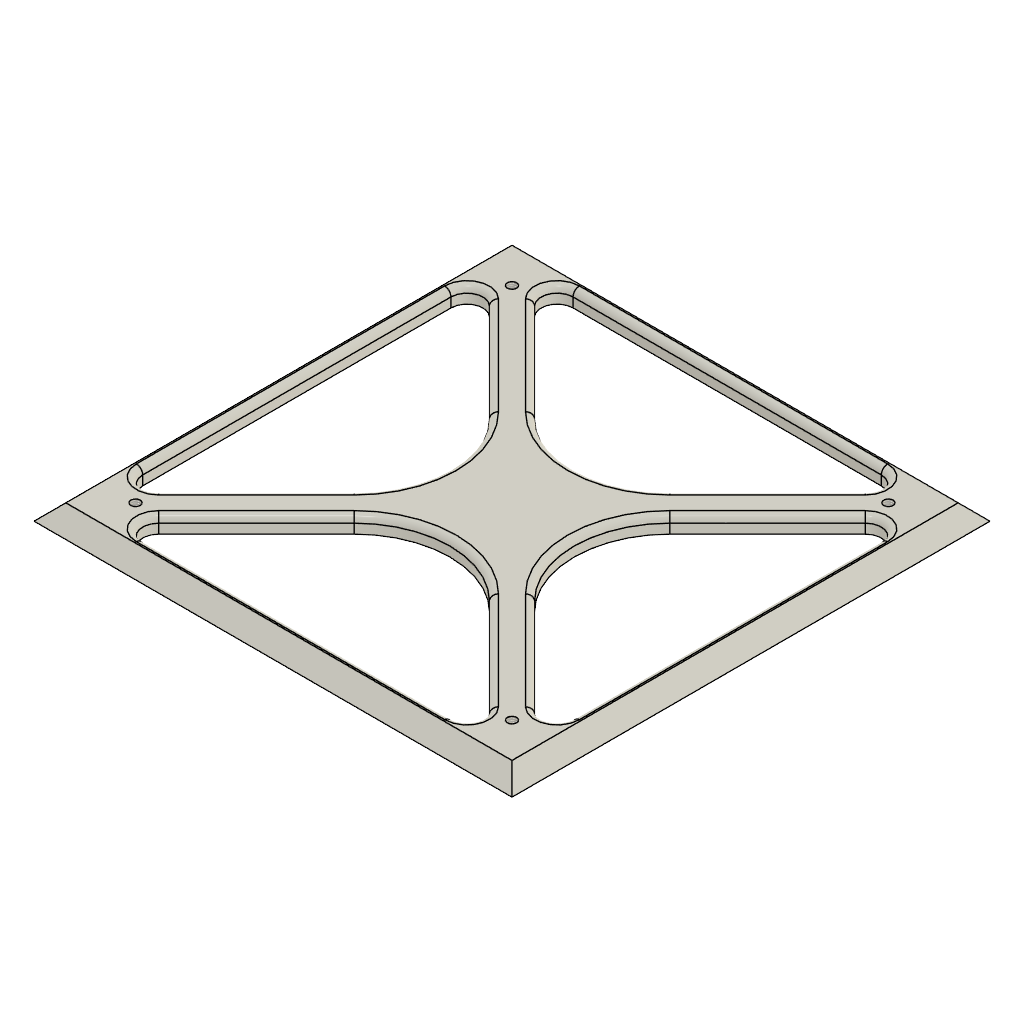
Cube_Bottom_Panel (Autodesk Fusion 360 design; units mm, degrees)
Autodesk Fusion 360 part; units mm, degrees
sketch "Sketch1" plane through (0, 0, 0) normal (0, 0, 1) x (1, 0, 0)
  line L0 (75, 75) -> (-75, 75)
  line L1 (-75, 75) -> (-75, -75)
  line L2 (-75, -75) -> (75, -75)
  line L3 (75, -75) -> (75, 75)
  line L4 (48.3579, -67.5) -> (-48.3579, -67.5)
  line L5 (-67.5, -48.3579) -> (-67.5, 48.3579)
  line L6 (-48.3579, 67.5) -> (48.3579, 67.5)
  line L7 (67.5, 48.3579) -> (67.5, -48.3579)
  line L8 (-58.9645, 51.8934) -> (-28.2843, 21.2132)
  line L9 (21.2132, -28.2843) -> (51.8934, -58.9645)
  line L10 (58.9645, -51.8934) -> (28.2843, -21.2132)
  line L11 (-21.2132, 28.2843) -> (-51.8934, 58.9645)
  line L12 (58.9645, 51.8934) -> (28.2843, 21.2132)
  line L13 (-21.2132, -28.2843) -> (-51.8934, -58.9645)
  line L14 (51.8934, 58.9645) -> (21.2132, 28.2843)
  line L15 (-28.2843, -21.2132) -> (-58.9645, -51.8934)
  arc A0 (21.2132, -28.2843) -> (-21.2132, -28.2843) centre (0, -49.4975) ccw
  arc A1 (-28.2843, -21.2132) -> (-28.2843, 21.2132) centre (-49.4975, 0) ccw
  arc A2 (-21.2132, 28.2843) -> (21.2132, 28.2843) centre (0, 49.4975) ccw
  arc A3 (28.2843, 21.2132) -> (28.2843, -21.2132) centre (49.4975, 0) ccw
  arc A4 (-48.3579, 67.5) -> (-51.8934, 58.9645) centre (-48.3579, 62.5) ccw
  arc A5 (-58.9645, 51.8934) -> (-67.5, 48.3579) centre (-62.5, 48.3579) ccw
  arc A6 (51.8934, 58.9645) -> (48.3579, 67.5) centre (48.3579, 62.5) ccw
  arc A7 (67.5, 48.3579) -> (58.9645, 51.8934) centre (62.5, 48.3579) ccw
  arc A8 (-67.5, -48.3579) -> (-58.9645, -51.8934) centre (-62.5, -48.3579) ccw
  arc A9 (-51.8934, -58.9645) -> (-48.3579, -67.5) centre (-48.3579, -62.5) ccw
  arc A10 (48.3579, -67.5) -> (51.8934, -58.9645) centre (48.3579, -62.5) ccw
  arc A11 (58.9645, -51.8934) -> (67.5, -48.3579) centre (62.5, -48.3579) ccw
  point P0 (-67.5, -67.5)
  point P1 (-67.5, 67.5)
  point P2 (67.5, 67.5)
  dimension "d1" = 150
  dimension "d2" = 150
  dimension "d3" = 135
  dimension "d4" = 135
  dimension "d9" = 30
  dimension "d10" = 30
  dimension "d11" = 30
  dimension "d12" = 30
  dimension "d13" = 5
  dimension "d14" = 5
  dimension "d15" = 5
  dimension "d16" = 5
  dimension "d17" = 5
  dimension "d18" = 5
  dimension "d19" = 5
  constraint horizontal L0
  constraint perpendicular L0 L1
  constraint parallel L0 L2
  constraint parallel L1 L3
  constraint horizontal L4
  constraint perpendicular L4 L5
  constraint parallel L4 L6
  constraint parallel L5 L7
  constraint tangent L13 A0
  constraint tangent L9 A0
  constraint tangent L15 A1
  constraint tangent L8 A1
  constraint tangent L11 A2
  constraint tangent L14 A2
  constraint tangent L10 A3
  constraint tangent L12 A3
  constraint coincident P1 L6
  constraint tangent L11 A4
  constraint tangent L6 A4
  constraint coincident P1 L5
  constraint tangent L8 A5
  constraint tangent L5 A5
  constraint coincident P2 L6
  constraint tangent L6 A6
  constraint tangent L14 A6
  constraint coincident P2 L7
  constraint tangent L12 A7
  constraint tangent L7 A7
  constraint coincident P0 L5
  constraint tangent L15 A8
  constraint tangent L5 A8
  constraint coincident P0 L4
  constraint tangent L13 A9
  constraint tangent L4 A9
  constraint equal A8 A9
  constraint tangent L4 A10
  constraint tangent L9 A10
  constraint tangent L10 A11
  constraint tangent L7 A11
  measures "d1" distance of L0.end L1.end
  measures "d2" distance of L1.end L2.end
  measures "d3" distance of P0 P1
  measures "d4" distance of P1 P2
  measures "d9" radius of A0
  measures "d10" radius of A1
  measures "d11" radius of A2
  measures "d12" radius of A3
  measures "d13" radius of A4
  measures "d14" radius of A5
  measures "d15" radius of A6
  measures "d16" radius of A7
  measures "d17" radius of A8
  measures "d18" radius of A10
  measures "d19" radius of A11
extrude "Extrude1" add sketch "Sketch1" along normal blind 5
chamfer "Chamfer1" distance 5 angle 45 4 edges at (75, 0, 5) (0, -75, 5) (-75, 0, 5) (0, 75, 5) tangent chain off
fillet "Fillet1" radius 2 24 edges at (36.5533, -43.6244, 5) (52.9773, -64.4134, 5) (0, -67.5, 5) (-52.9773, -64.4134, 5) (-36.5533, -43.6244, 5) (0, -19.4975, 5) (-64.4134, -52.9773, 5) (-67.5, 0, 5) (-64.4134, 52.9773, 5) (-43.6244, 36.5533, 5) (-19.4975, 0, 5) (-43.6244, -36.5533, 5) (-52.9773, 64.4134, 5) (0, 67.5, 5) (52.9773, 64.4134, 5) (36.5533, 43.6244, 5) (0, 19.4975, 5) (-36.5533, 43.6244, 5) (64.4134, 52.9773, 5) (67.5, 0, 5) (64.4134, -52.9773, 5) (43.6244, -36.5533, 5) (19.4975, 0, 5) (43.6244, 36.5533, 5)
sketch "Sketch4" plane through (0, 0, 0) normal (0, 0, -1) x (1, 0, 0)
  arc A0 (-21.2132, 28.2843) -> (21.2132, 28.2843) centre (0, 49.4975) ccw
  line L0 (-21.2132, 28.2843) -> (-51.8934, 58.9645)
  arc A1 (-48.3579, 67.5) -> (-51.8934, 58.9645) centre (-48.3579, 62.5) ccw
  line L1 (-48.3579, 67.5) -> (48.3579, 67.5)
  arc A2 (51.8934, 58.9645) -> (48.3579, 67.5) centre (48.3579, 62.5) ccw
  line L2 (51.8934, 58.9645) -> (21.2132, 28.2843)
  arc A3 (58.9645, -51.8934) -> (67.5, -48.3579) centre (62.5, -48.3579) ccw
  line L3 (58.9645, -51.8934) -> (28.2843, -21.2132)
  arc A4 (28.2843, 21.2132) -> (28.2843, -21.2132) centre (49.4975, 0) ccw
  line L4 (28.2843, 21.2132) -> (58.9645, 51.8934)
  arc A5 (67.5, 48.3579) -> (58.9645, 51.8934) centre (62.5, 48.3579) ccw
  line L5 (67.5, 48.3579) -> (67.5, -48.3579)
  arc A6 (-67.5, -48.3579) -> (-58.9645, -51.8934) centre (-62.5, -48.3579) ccw
  line L6 (-67.5, -48.3579) -> (-67.5, 48.3579)
  arc A7 (-58.9645, 51.8934) -> (-67.5, 48.3579) centre (-62.5, 48.3579) ccw
  line L7 (-58.9645, 51.8934) -> (-28.2843, 21.2132)
  arc A8 (-28.2843, -21.2132) -> (-28.2843, 21.2132) centre (-49.4975, 0) ccw
  line L8 (-28.2843, -21.2132) -> (-58.9645, -51.8934)
  arc A9 (21.2132, -28.2843) -> (-21.2132, -28.2843) centre (0, -49.4975) ccw
  line L9 (21.2132, -28.2843) -> (51.8934, -58.9645)
  arc A10 (48.3579, -67.5) -> (51.8934, -58.9645) centre (48.3579, -62.5) ccw
  line L10 (48.3579, -67.5) -> (-48.3579, -67.5)
  arc A11 (-51.8934, -58.9645) -> (-48.3579, -67.5) centre (-48.3579, -62.5) ccw
  line L11 (-51.8934, -58.9645) -> (-21.2132, -28.2843)
  line L12 (75, -75) -> (75, 75)
  line L13 (75, 75) -> (-75, 75)
  line L14 (-75, 75) -> (-75, -75)
  line L15 (-75, -75) -> (75, -75)
  arc A12 (-53.3076, -57.5503) -> (-48.3579, -69.5) centre (-48.3579, -62.5) ccw
  line L16 (-48.3579, -69.5) -> (48.3579, -69.5)
  arc A13 (48.3579, -69.5) -> (53.3076, -57.5503) centre (48.3579, -62.5) ccw
  line L17 (53.3076, -57.5503) -> (22.6274, -26.8701)
  arc A14 (22.6274, -26.8701) -> (-22.6274, -26.8701) centre (0, -49.4975) ccw
  line L18 (-22.6274, -26.8701) -> (-53.3076, -57.5503)
  line L19 (22.6274, 26.8701) -> (53.3076, 57.5503)
  arc A15 (53.3076, 57.5503) -> (48.3579, 69.5) centre (48.3579, 62.5) ccw
  line L20 (48.3579, 69.5) -> (-48.3579, 69.5)
  arc A16 (-48.3579, 69.5) -> (-53.3076, 57.5503) centre (-48.3579, 62.5) ccw
  line L21 (-53.3076, 57.5503) -> (-22.6274, 26.8701)
  arc A17 (-22.6274, 26.8701) -> (22.6274, 26.8701) centre (0, 49.4975) ccw
  line L22 (-70, -70) -> (-70, 70)
  line L23 (-70, 70) -> (70, 70)
  line L24 (70, 70) -> (70, -70)
  line L25 (70, -70) -> (-70, -70)
  arc A18 (-57.5503, 53.3076) -> (-69.5, 48.3579) centre (-62.5, 48.3579) ccw
  line L26 (-69.5, 48.3579) -> (-69.5, -48.3579)
  arc A19 (-69.5, -48.3579) -> (-57.5503, -53.3076) centre (-62.5, -48.3579) ccw
  line L27 (-57.5503, -53.3076) -> (-26.8701, -22.6274)
  arc A20 (-26.8701, -22.6274) -> (-26.8701, 22.6274) centre (-49.4975, 0) ccw
  line L28 (-26.8701, 22.6274) -> (-57.5503, 53.3076)
  arc A21 (57.5503, -53.3076) -> (69.5, -48.3579) centre (62.5, -48.3579) ccw
  line L29 (69.5, -48.3579) -> (69.5, 48.3579)
  arc A22 (69.5, 48.3579) -> (57.5503, 53.3076) centre (62.5, 48.3579) ccw
  line L30 (57.5503, 53.3076) -> (26.8701, 22.6274)
  arc A23 (26.8701, 22.6274) -> (26.8701, -22.6274) centre (49.4975, 0) ccw
  line L31 (26.8701, -22.6274) -> (57.5503, -53.3076)
  line L32 (70, 70) -> (59.05, 70)
  line L33 (59.05, 70) -> (59.05, 59.05)
  line L34 (-70, 70) -> (-59.05, 70) construction
  line L35 (-59.05, 70) -> (-59.05, 59.05)
  line L36 (-70, -70) -> (-59.05, -70)
  line L37 (-59.05, -70) -> (-59.05, -59.05)
  line L38 (70, -70) -> (59.05, -70)
  line L39 (59.05, -70) -> (59.05, -59.05)
  circle A24 centre (59.05, 59.05) radius 1.5
  circle A25 centre (-59.05, 59.05) radius 1.5
  circle A26 centre (-59.05, -59.05) radius 1.5
  circle A27 centre (59.05, -59.05) radius 1.5
  dimension "d25" = 10.95
  dimension "d26" = 10.95
  dimension "d27" = 10.95
  dimension "d28" = 10.95
  dimension "d29" = 10.95
  dimension "d30" = 10.95
  dimension "d31" = 10.95
  dimension "d32" = 10.95
  dimension "d33" = 3
  dimension "d34" = 3
  dimension "d35" = 3
  dimension "d36" = 3
  constraint coincident L23.end L24.start
  constraint perpendicular L24 L32
  constraint perpendicular L32 L33
  constraint coincident L22.end L23.start
  constraint perpendicular L22 L34
  constraint perpendicular L23 L35
  constraint coincident L22.start L25.end
  constraint perpendicular L22 L36
  constraint perpendicular L36 L37
  constraint coincident L24.end L25.start
  constraint perpendicular L24 L38
  constraint perpendicular L38 L39
  constraint coincident L33.end A24.centre
  constraint coincident L35.end A25.centre
  constraint coincident L37.end A26.centre
  constraint coincident L39.end A27.centre
  measures "d25" distance of L23.end L32.end
  measures "d26" distance of L32.end L33.end
  measures "d27" distance of L22.end L34.end
  measures "d28" distance of L34.end L35.end
  measures "d29" distance of L22.start L36.end
  measures "d30" distance of L36.end L37.end
  measures "d31" distance of L24.end L38.end
  measures "d32" distance of L38.end L39.end
  measures "d33" diameter of A24
  measures "d34" diameter of A25
  measures "d35" diameter of A26
  measures "d36" diameter of A27
hole "Hole1" at (-59.05, -59.05, 0) at (59.05, -59.05, 0) at (59.05, 59.05, 0) at (-59.05, 59.05, 0) direction (0, 0, 1) diameter 2.93 depth 5 tip angle 180 countersink diameter 5.2 countersink angle 90
thread "Thread1" "ISO Metric profile 3.5 M3.5x0.6 M3.5x0.6 6H" major diameter 3.5995 minor diameter 2.93 pitch 0.6 angle 60 resizes the face on face at (60.1484, 58.0806, 2.4233) on face at (-57.9516, -60.0194, 2.4233) on face at (60.1484, -60.0194, 2.4233) on face at (-57.9516, 58.0806, 2.4233)
